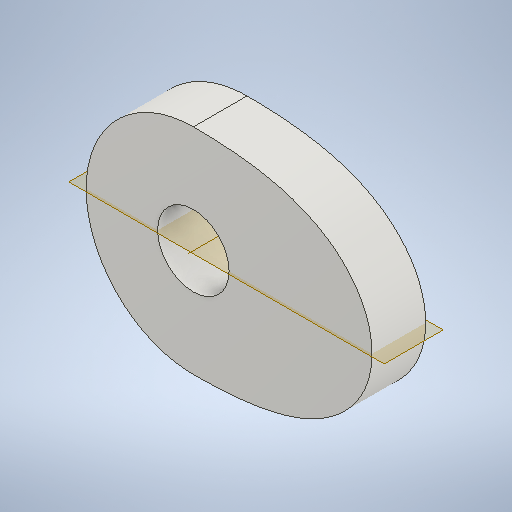
# Autodesk Inventor part: Disc Cam
Saved by Autodesk Inventor 2025.2 (Build 292293000, 293)
## iProperties
CustomPartVersion: 1
Created: 2025-05-17
Part Number: Disc Cam
Material: Stainless Steel, Austenitic
Document SubType Name: Modeling
Designer: laura
Manufacturer: Standard
Standards Organization: Custom
Density: 1 g/cm^3
Appearance: Steel
Author: laura
Autodesk Inventor part; units mm, degrees
ref_plane "YZ Plane" through (0, 0, 0) normal (1, 0, 0) x (0, 1, 0)
ref_plane "XY Plane" through (0, 0, 0) normal (0, 0, 1) x (1, 0, 0)
sketch "Main Sketch" plane through (0, 0, 0) normal (0, 0, 1) x (1, 0, 0)
  spline S0 degree 5 poles (0, 12) (0.4327, 12.0041) (1.238, 11.9943) (2.6888, 11.9527) (4.1109, 11.8701) (6.2022, 11.6677) (7.992, 11.3887) (9.8408, 10.9799) (11.5662, 10.4426) (13.1917, 9.7653) (14.6863, 8.9436) (16.037, 7.9785) (17.2209, 6.8782) (18.2192, 5.657) (19.0138, 4.3344) (19.5911, 2.9336) (19.9412, 1.4801) (20.0585, 0) (19.9412, -1.4801) (19.5911, -2.9336) (19.0138, -4.3344) (18.2192, -5.657) (17.2209, -6.8782) (16.0369, -7.9785) (14.6863, -8.9436) (13.1916, -9.7653) (11.5663, -10.4426) (9.8405, -10.98) (7.9929, -11.3886) (6.1398, -11.6773) (4.1046, -11.8695) (2.4108, -11.969) (0.0573, -12.0214) (-1.037, -11.9933) (-2.476, -11.7821) (-3.6924, -11.4502) (-4.8995, -10.9922) (-6.0142, -10.421) (-7.0738, -9.7348) (-8.0512, -8.9423) (-8.9424, -8.0516) (-9.7348, -7.0728) (-10.4209, -6.0165) (-10.9926, -4.8942) (-11.444, -3.7184) (-11.77, -2.5018) (-11.967, -1.2578) (-12.0329, 0) (-11.967, 1.2578) (-11.77, 2.5018) (-11.444, 3.7184) (-10.9926, 4.8942) (-10.4209, 6.0165) (-9.7347, 7.0728) (-8.9425, 8.0516) (-8.051, 8.9423) (-7.0743, 9.7348) (-6.013, 10.4211) (-4.9023, 10.9921) (-3.7478, 11.4272) (-2.5909, 11.7553) (-1.4933, 11.9256) (-0.8468, 11.9813) (-0.3375, 11.9968) (0, 12) knots 0 0 0 0 0 0 0.023602 0.039175 0.058493 0.077535 0.09627 0.114695 0.132824 0.150677 0.168275 0.185637 0.202784 0.219743 0.236548 0.253244 0.269882 0.286521 0.303216 0.320021 0.33698 0.354127 0.371489 0.389087 0.40694 0.425069 0.443495 0.462229 0.481271 0.500589 0.51923 0.537128 0.554217 0.570447 0.585788 0.601129 0.61647 0.631811 0.647153 0.662494 0.677835 0.693176 0.708517 0.723858 0.7392 0.754541 0.769882 0.785223 0.800564 0.815906 0.831247 0.846588 0.861929 0.87727 0.892612 0.907953 0.923294 0.938635 0.953976 0.969318 0.981591 1 1 1 1 1 1
  point P0 (4.1438, 11.849)
  point P1 (6.1384, 11.6478)
  point P2 (8.0539, 11.3462)
  point P3 (9.8782, 10.9299)
  point P4 (11.6015, 10.3855)
  point P5 (13.2125, 9.7035)
  point P6 (14.696, 8.8789)
  point P7 (16.0336, 7.9134)
  point P8 (17.2051, 6.8154)
  point P9 (18.1907, 5.5998)
  point P10 (18.9738, 4.2867)
  point P11 (19.5413, 2.8992)
  point P12 (19.885, 1.462)
  point P13 (20, 0)
  point P14 (19.885, -1.462)
  point P15 (19.5413, -2.8992)
  point P16 (18.9738, -4.2867)
  point P17 (18.1907, -5.5998)
  point P18 (17.2051, -6.8154)
  point P19 (16.0336, -7.9134)
  point P20 (14.696, -8.8789)
  point P21 (13.2125, -9.7035)
  point P22 (11.6015, -10.3855)
  point P23 (9.8782, -10.9299)
  point P24 (8.0539, -11.3462)
  point P25 (6.1384, -11.6478)
  point P26 (4.1438, -11.849)
  point P27 (2.0886, -11.9631)
  point P28 (0, -12)
  point P29 (-1.2543, -11.9343)
  point P30 (-2.4949, -11.7378)
  point P31 (-3.7082, -11.4127)
  point P32 (-4.8808, -10.9625)
  point P33 (-6, -10.3923)
  point P34 (-7.0534, -9.7082)
  point P35 (-8.0296, -8.9177)
  point P36 (-8.9177, -8.0296)
  point P37 (-9.7082, -7.0534)
  point P38 (-10.3923, -6)
  point P39 (-10.9625, -4.8808)
  point P40 (-11.4127, -3.7082)
  point P41 (-11.7378, -2.4949)
  point P42 (-11.9343, -1.2543)
  point P43 (-12, 0)
  point P44 (-11.9343, 1.2543)
  point P45 (-11.7378, 2.4949)
  point P46 (-11.4127, 3.7082)
  point P47 (-10.9625, 4.8808)
  point P48 (-10.3923, 6)
  point P49 (-9.7082, 7.0534)
  point P50 (-8.9177, 8.0296)
  point P51 (-8.0296, 8.9177)
  point P52 (-7.0534, 9.7082)
  point P53 (-6, 10.3923)
  point P54 (-4.8808, 10.9625)
  point P55 (-3.7082, 11.4127)
  point P56 (-2.4949, 11.7378)
  point P57 (-1.2543, 11.9343)
  constraints: 60 other
extrude "Cam" add sketch "Main Sketch" along normal blind 6
sketch "Sketch3" plane through (0, 0, 6) normal (0, 0, 1) x (1, 0, 0)
  circle A0 centre (0, 0) radius 4
  dimension "d4" = 8
  constraints: 1 centre point, 1 coincident
  measures "d4" diameter of A0
extrude "Extrusion2" cut sketch "Sketch3" against normal through all
body "Solid1"
